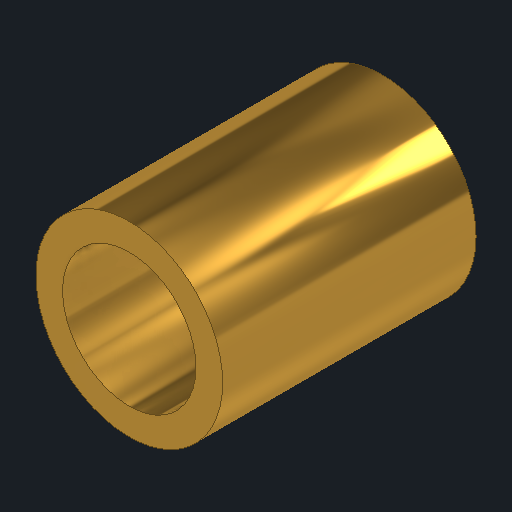
# Autodesk Inventor part: insert_m3_heatset_drive
Saved by Autodesk Inventor 2027.1 (Build 311270010, 270A)
## iProperties
Created: 2026-11-04
Part Number: insert_m3_heatset_drive
Material: Generic
Description: M3 heat-set insert, 4.2 hole x 5.7 (in the RA-motor frame copy)
Document SubType Name: Modeling
Designer: Claude (from photos)
Density: 1 g/cm^3
Appearance: Brass - Polished
Author: alexg
Autodesk Inventor part; units mm, degrees
ref_plane "YZ Plane" through (0, 0, 0) normal (1, 0, 0) x (0, 1, 0)
ref_plane "XZ Plane" through (0, 0, 0) normal (0, 1, 0) x (-1, 0, 0)
ref_plane "XY Plane" through (0, 0, 0) normal (0, 0, 1) x (1, 0, 0)
sketch "Insert sketch" plane through (0, 0, 0) normal (0, 0, 1) x (1, 0, 0)
  circle A0 centre (0, 0) radius 2.1
  circle A1 centre (0, 0) radius 1.5
  dimension "d0" = 5.7
  constraints: 2 centre point
extrude "Insert" add sketch "Insert sketch" along normal blind 5.7
body "Solid1"
